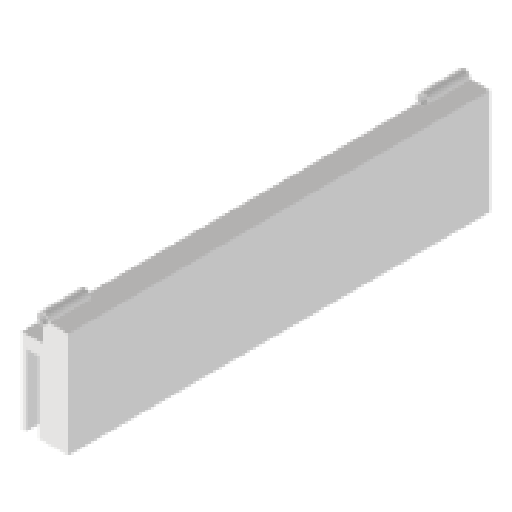
# Autodesk Inventor part: BISAGRA tope
Saved by Autodesk Inventor 2025.2 (Build 292293000, 293)
## iProperties
Created: 2026-09-20
Part Number: BISAGRA tope
Material: Genérico
Document SubType Name: Modeling
Designer: autor
Density: 1 g/cm^3
Appearance: Valor por defecto
Author: autor
Autodesk Inventor part; units mm, degrees
ref_plane "YZ Plane" through (0, 0, 0) normal (1, 0, 0) x (0, 1, 0)
ref_plane "XZ Plane" through (0, 0, 0) normal (0, 1, 0) x (-1, 0, 0)
sketch "Boceto1" plane through (0, 0, 0) normal (0, 0, 1) x (1, 0, 0)
  line L0 (-11.765, -5.5123) -> (-11.765, 14.4877)
  line L1 (-11.765, 14.4877) -> (-6.765, 14.4877)
  line L2 (-6.765, 14.4877) -> (-6.765, 19.4877)
  line L3 (-6.765, 19.4877) -> (-0.765, 19.4877)
  line L4 (-0.765, 19.4877) -> (-0.765, -5.5123)
  line L5 (-0.765, -5.5123) -> (-7.765, -5.5123)
  line L6 (-7.765, -5.5123) -> (-7.765, 11.4877)
  line L7 (-7.765, 11.4877) -> (-10.765, 11.4877)
  line L8 (-10.765, 11.4877) -> (-10.765, -5.5123)
  line L9 (-10.765, -5.5123) -> (-11.765, -5.5123)
  point P0 (0, 0)
  dimension "d0" = 20
  dimension "d1" = 5
  dimension "d2" = 5
  dimension "d3" = 6
  dimension "d8" = 7
  dimension "d9" = 17
  dimension "d10" = 3
  dimension "d13" = 25
  constraints: 20 end point, 4 perpendicular, 2 horizontal, 2 parallel, 1 point on line, 1 vertical
  measures "d0" distance of L0.start L0.end
  measures "d1" distance of L0.end L1.end
  measures "d2" distance of L1.end L2.end
  measures "d3" distance of L2.end L3.end
  measures "d8" distance of L4.end L5.end
  measures "d9" distance of L5.end L6.end
  measures "d10" distance of L6.end L7.end
  measures "d13" distance of L3.end L4.end
extrude "Extrusión1" add sketch "Boceto1" along normal blind 100
sketch "Boceto2" plane through (0, 0, 0) normal (0, 0, -1) x (-1, 0, 0)
  line L0 (0.765, 19.4877) -> (6.765, 19.4877) projected
  circle A0 centre (6.765, 19.4877) radius 4
  point P0 (0, 0)
  dimension "d14" = 8
  constraints: 1 centre point
  measures "d14" diameter of A0
extrude "Extrusión2" add sketch "Boceto2" against normal up to surface (100 mm away)
sketch "Boceto3" plane through (0, 0, 0) normal (0, 0, -1) x (-1, 0, 0)
  line L0 (6.765, 15.4877) -> (6.765, 14.4877) projected
  arc A0 (6.765, 17.4877) -> (4.765, 19.4877) centre (6.765, 19.4877) ccw
  line L1 (3.765, 19.4877) -> (4.765, 19.4877)
  line L2 (6.765, 17.4877) -> (6.765, 16.4877)
  arc A1 (9.7093, 20.0633) -> (5.8252, 16.6387) centre (6.765, 19.4877) ccw projected
  arc A2 (3.765, 19.4877) -> (6.765, 16.4877) centre (6.765, 19.4877) ccw
  point P0 (0, 0)
  point P1 (5.8252, 16.6387)
  dimension "d21" = 4
  constraints: 5 point on circle, 4 end point, 2 centre point, 1 coincident, 1 horizontal, 1 perpendicular
  measures "d21" diameter of A0
extrude "Extrusión3" cut sketch "Boceto3" against normal through all
ref_plane "Plano de trabajo1" through (0, 0, 90) normal (0, 0, 1) x (1, 0, 0)
sketch "Boceto6" plane through (0, 0, 90) normal (0, 0, 1) x (1, 0, 0)
  arc A0 (-2.765, 19.4877) -> (-6.765, 15.4877) centre (-6.765, 19.4877) ccw projected
  arc A1 (-2.765, 19.4877) -> (-6.765, 15.4877) centre (-6.765, 19.4877) ccw
  arc A2 (-5.515, 19.4877) -> (-6.765, 18.2377) centre (-6.765, 19.4877) ccw
  line L0 (-2.765, 19.4877) -> (-5.515, 19.4877)
  line L1 (-6.765, 18.2377) -> (-6.765, 15.4877)
  point P0 (0, 0)
  constraints: 4 end point, 4 point on circle, 2 centre point, 2 coincident, 1 horizontal
extrude "Extrusión5" cut sketch "Boceto6" against normal blind 80
ref_plane "Plano de trabajo2" through (0, 0, 89.5) normal (0, 0, 1) x (1, 0, 0)
fillet "Empalme2" radius 2 2 edges at (-2.765, 19.4877, 5) (-2.765, 19.4877, 95)
fillet "Empalme3" radius 1 2 edges at (-6.765, 15.4877, 5) (-6.765, 15.4877, 95)
